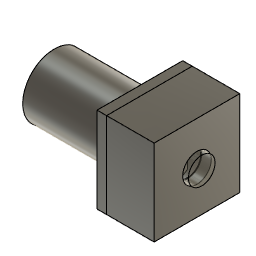
external_led_holder v3 (Autodesk Fusion 360 design; units mm, degrees)
Autodesk Fusion 360 part; units mm, degrees
sketch "Sketch1" plane through (0, 0, 0) normal (1, 0, 0) x (0, 1, 0)
  circle A0 centre (14, 14) radius 6.62
  line L0 (12, 17.5) -> (10.5, 17.5)
  line L1 (5, 23) -> (23, 23)
  line L2 (23, 23) -> (23, 5)
  line L3 (23, 5) -> (5, 5)
  line L4 (5, 5) -> (5, 23)
  line L5 (18, 20) -> (18, 8)
  circle A1 centre (14, 14) radius 3
  line L6 (10.5, 17.5) -> (17.5, 17.5)
  line L7 (17.5, 17.5) -> (17.5, 10.5)
  line L8 (17.5, 10.5) -> (10.5, 10.5)
  line L9 (10.5, 10.5) -> (10.5, 17.5)
  line L10 (10.5, 17.5) -> (17.5, 10.5) construction
  line L11 (17.5, 17.5) -> (10.5, 10.5) construction
  point P0 (14, 14)
  dimension "d1" = 13.24
  dimension "d8" = 6
  constraint horizontal L0
  constraint horizontal L1
  constraint vertical L2
  constraint horizontal L3
  constraint vertical L4
  constraint vertical L5
  constraint concentric A0 A1
  constraint horizontal L6
  constraint perpendicular L6 L7
  constraint parallel L6 L8
  constraint parallel L7 L9
  constraint coincident L10 P0
  constraint coincident L11 P0
  constraint coincident P0 A0.centre
  measures "d1" diameter of A0
  measures "d8" diameter of A1
extrude "Extrude1" add sketch "Sketch1" against normal blind 2 contours L1 L2 L3 L4 makes body 1
extrude "Extrude2" add sketch "Sketch1" along normal blind 4 and the other way blind 20 contours A0 L5 | L0 L6 L7 L8 L9 | A1 picked at (9.46, 14) bodies 1
extrude "Extrude3" add sketch "Sketch1" along normal blind 10 and the other way blind -8 separate body contours A0 L5 | A0 L5 | L0 L6 L7 L8 L9 | L1 L2 L3 L4 makes body 2
extrude "Extrude4" add sketch "Sketch1" along normal blind 8 contours L1 L2 L3 L4 bodies 2
extrude "Extrude5" add sketch "Sketch1" along normal blind 11 and the other way blind -7.4 separate body contours A1 makes body 3
extrude "Extrude6" add sketch "Sketch1" along normal blind 8 and the other way blind -7.4 contours L0 L6 L7 L8 L9 bodies 3
move_face "OffsetFaces1" offset -0.2 1 faces at (9, 16.9851, 13.7013) on bodies 3
move_face "OffsetFaces2" offset -0.2 1 faces at (2.6667, 20.5871, 13.3409) on bodies 2
named bodies: "led_body", "led_cap", "led_lens"
